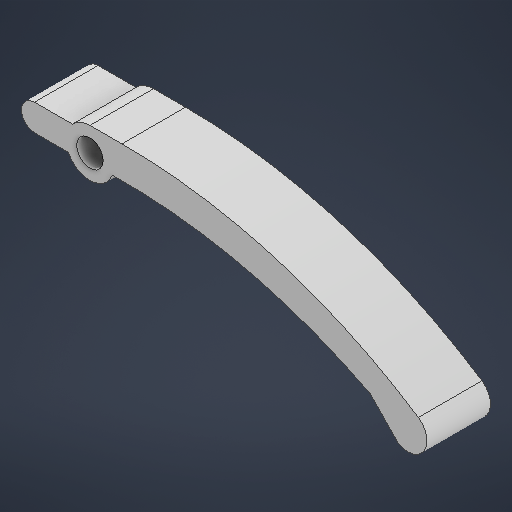
# Autodesk Inventor part: 6_12_piece_mobile_detection5
Saved by Autodesk Inventor 2026 (Build 300175000, 175)
## iProperties
Created: 2025-06-25
Part Number: 6_12_piece_mobile_detection5
Material: Générique
Document SubType Name: Modeling
Designer: virgi
Density: 1 g/cm^3
Appearance: Par défaut
Author: virgi
Autodesk Inventor part; units mm, degrees
ref_plane "YZ Plane" through (0, 0, 0) normal (1, 0, 0) x (0, 1, 0)
ref_plane "XZ Plane" through (0, 0, 0) normal (0, 1, 0) x (-1, 0, 0)
ref_plane "XY Plane" through (0, 0, 0) normal (0, 0, 1) x (1, 0, 0)
sketch "Esquisse1" plane through (0, 0, 0) normal (0, 0, 1) x (1, 0, 0)
  arc A0 (28.2117, -7.4172) -> (30.9886, -6.1178) centre (30, -7.6219) ccw
  line L0 (0, 0) -> (37.0112, 0) construction
  line L1 (3.022, 2.25) -> (0, 2.25)
  arc A1 (-5.2293, 1.5319) -> (-5.2293, -0.9678) centre (-5.2113, 0.2821) ccw
  line L2 (-5.2293, 1.5319) -> (-5.2293, -0.9678) construction
  arc A2 (30.9886, -6.1178) -> (3.022, 2.25) centre (3.022, -48.6689) ccw
  arc A3 (28.2117, -7.4172) -> (2.1185, -0.758) centre (3.022, -51.6689) ccw
  line L3 (3.022, -23.6917) -> (3.022, -47.2006) construction
  line L4 (-5.2293, -0.9678) -> (-2.0312, -0.9678)
  line L5 (-5.2293, 1.5319) -> (-1.6479, 1.5319)
  arc A4 (0, 2.25) -> (-1.6479, 1.5319) centre (0, 0) ccw
  arc A5 (-2.0312, -0.9678) -> (2.1185, -0.758) centre (0, 0) ccw
  point P0 (30.7629, -9.2523)
  dimension "d2" = 1.8
  dimension "d19" = 1.25
  dimension "d22" = 30
  dimension "d23" = 3
  dimension "d24" = 9.872
  constraints: 13 point on circle, 12 end point, 6 centre point, 4 horizontal, 2 coincident, 2 point on line, 2 vertical, 1 equal radius, 1 tangent
  measures "d2" radius of A0
  measures "d19" radius of A1
  measures "d22" horizontal distance of A0.centre point (0, 0)
  measures "d23" distance of A3.centre A2.centre
  measures "d24" distance from line of A0.centre L1
extrude "Extrusion1" add sketch "Esquisse1" along normal blind 6
sketch "Esquisse2" plane through (0, 0, 6) normal (0, 0, 1) x (1, 0, 0)
  point P0 (0, 0)
  point P1 (0, 0)
  constraints: 1 coincident
hole "Perçage1" at (0, 0, 6) direction (0, 0, -1) diameter 2.5 end through all
chamfer "Chanfrein1" distance 2 angle 45 1 edges at (28.2117, -7.4172, 3)
